Autodesk Fusion 360 part; units mm, degrees
(part 3 of 6)
sketch "Sketch1" plane through (0, 0, 0) normal (0, 1, 0) x (1, 0, 0)
  line L0 (-76.2, 57.15) -> (-76.2, -57.15) construction
  line L1 (76.2, -49.53) -> (76.2, 45.72) construction
  line L2 (-76.2, 57.15) -> (-38.1, 57.15) construction
  line L3 (-38.1, 57.15) -> (-38.1, 62.865) construction
  line L4 (-38.1, 62.865) -> (-19.05, 62.865) construction
  line L5 (-19.05, 62.865) -> (-19.05, 55.245) construction
  line L6 (-19.05, 55.245) -> (0, 55.245) construction
  line L7 (0, 55.245) -> (0, 45.72) construction
  line L8 (0, 45.72) -> (19.05, 45.72) construction
  line L9 (19.05, 45.72) -> (38.1, 45.72) construction
  line L10 (38.1, 45.72) -> (57.15, 45.72) construction
  line L11 (57.15, 45.72) -> (76.2, 45.72) construction
  line L12 (-57.15, 57.15) -> (-57.15, 38.1) construction
  line L13 (-57.15, 38.1) -> (-76.2, 38.1) construction
  line L14 (-38.1, 57.15) -> (-38.1, -38.1) construction
  line L15 (-38.1, -38.1) -> (-76.2, -38.1) construction
  line L16 (-57.15, 38.1) -> (-76.2, 57.15) construction
  line L17 (-76.2, 38.1) -> (-57.15, 57.15) construction
  line L18 (-19.05, 55.245) -> (-19.05, 43.815) construction
  line L19 (-19.05, 43.815) -> (-38.1, 43.815) construction
  line L20 (-38.1, 43.815) -> (-19.05, 62.865) construction
  line L21 (-19.05, 43.815) -> (-38.1, 62.865) construction
  line L22 (-19.05, 43.815) -> (-19.05, -32.385) construction
  line L23 (-19.05, -32.385) -> (-38.1, -32.385) construction
  line L24 (0, 45.72) -> (0, 36.195) construction
  line L25 (0, 36.195) -> (-19.05, 36.195) construction
  line L26 (0, 36.195) -> (-19.05, 55.245) construction
  line L27 (0, 55.245) -> (-19.05, 36.195) construction
  line L28 (0, 36.195) -> (0, -59.055) construction
  line L29 (0, -59.055) -> (-19.05, -59.055) construction
  line L30 (-19.05, -59.055) -> (-19.05, -32.385) construction
  line L31 (19.05, 45.72) -> (19.05, 26.67) construction
  line L32 (19.05, 26.67) -> (0, 26.67) construction
  line L33 (38.1, 45.72) -> (38.1, -68.58) construction
  line L34 (38.1, -68.58) -> (0, -68.58) construction
  line L35 (0, -68.58) -> (0, -59.055) construction
  line L36 (38.1, -68.58) -> (57.15, -68.58) construction
  line L37 (57.15, -68.58) -> (57.15, -49.53) construction
  line L38 (57.15, -49.53) -> (76.2, -49.53) construction
  line L39 (57.15, -49.53) -> (38.1, -49.53) construction
  line L40 (-76.2, -57.15) -> (-19.05, -57.15) construction
  line L41 (38.1, 45.72) -> (38.1, 26.67) construction
  line L42 (38.1, 26.67) -> (38.1, 7.62) construction
  line L43 (38.1, 7.62) -> (76.2, 7.62) construction
  line L44 (38.1, 26.67) -> (57.15, 26.67) construction
  line L45 (57.15, 26.67) -> (57.15, 45.72) construction
  line L46 (57.15, 26.67) -> (38.1, 45.72) construction
  line L47 (38.1, 26.67) -> (57.15, 45.72) construction
  line L48 (57.15, 7.62) -> (57.15, -30.48) construction
  line L49 (57.15, -30.48) -> (38.1, -30.48) construction
  line L50 (38.1, -11.43) -> (57.15, -11.43) construction
  line L51 (57.15, -30.48) -> (76.2, -30.48) construction
  line L52 (38.1, 7.62) -> (57.15, -11.43) construction
  line L53 (57.15, 7.62) -> (38.1, -11.43) construction
  line L54 (38.1, -49.53) -> (57.15, -68.58) construction
  line L55 (57.15, -49.53) -> (38.1, -68.58) construction
  line L56 (19.05, 45.72) -> (0, 26.67) construction
  line L57 (19.05, 26.67) -> (0, 45.72) construction
  line L58 (38.1, -30.48) -> (76.2, -49.53) construction
  line L59 (76.2, -30.48) -> (38.1, -49.53) construction
  line L60 (57.15, -30.48) -> (57.15, -49.53) construction
  line L61 (57.15, 7.62) -> (76.2, -30.48) construction
  line L62 (76.2, 7.62) -> (57.15, -30.48) construction
  line L63 (57.15, -11.43) -> (76.2, -11.43) construction
  line L64 (-19.05, -59.055) -> (-19.05, -59.16) construction
  line L65 (-19.05, -59.16) -> (-19.115, -59.16) construction
  line L66 (-19.115, -59.16) -> (-19.2509, -58.6529) construction
  line L67 (-19.2509, -58.6529) -> (-18.7438, -58.517) construction
  line L68 (-18.7438, -58.517) -> (-37.1447, -63.4475) construction
  line L69 (-37.1447, -63.4475) -> (-32.2142, -81.8484) construction
  line L70 (-32.2142, -81.8484) -> (-13.8133, -76.9179) construction
  line L71 (-13.8133, -76.9179) -> (-18.7438, -58.517) construction
  line L72 (-37.1447, -63.4475) -> (-73.9464, -73.3085) construction
  line L73 (-73.9464, -73.3085) -> (-64.0854, -110.1103) construction
  line L74 (-64.0854, -110.1103) -> (-8.8828, -95.3188) construction
  line L75 (-8.8828, -95.3188) -> (-13.8133, -76.9179) construction
  line L76 (-18.7438, -58.517) -> (-32.2142, -81.8484) construction
  line L77 (-37.1447, -63.4475) -> (-13.8133, -76.9179) construction
  line L78 (-20.5292, -61.6095) -> (-34.0522, -65.233)
  line L79 (-34.0522, -65.233) -> (-30.4287, -78.7559)
  line L80 (-30.4287, -78.7559) -> (-16.9057, -75.1325)
  line L81 (-16.9057, -75.1325) -> (-20.5292, -61.6095)
  line L82 (-20.5292, -61.6095) -> (-30.4287, -78.7559) construction
  line L83 (-34.0522, -65.233) -> (-16.9057, -75.1325) construction
  line L84 (-48.8296, -83.6864) -> (-35.3066, -80.063)
  line L85 (-35.3066, -80.063) -> (-38.9301, -66.54)
  line L86 (-38.9301, -66.54) -> (-52.4531, -70.1635)
  line L87 (-52.4531, -70.1635) -> (-48.8296, -83.6864)
  line L88 (-67.2305, -88.6169) -> (-53.7075, -84.9935)
  line L89 (-53.7075, -84.9935) -> (-57.331, -71.4705)
  line L90 (-57.331, -71.4705) -> (-70.8539, -75.094)
  line L91 (-70.8539, -75.094) -> (-67.2305, -88.6169)
  line L92 (-25.4982, -97.1568) -> (-11.9752, -93.5333)
  line L93 (-11.9752, -93.5333) -> (-15.5987, -80.0104)
  line L94 (-15.5987, -80.0104) -> (-29.1217, -83.6338)
  line L95 (-29.1217, -83.6338) -> (-25.4982, -97.1568)
  line L96 (-43.8991, -102.0873) -> (-30.3761, -98.4638)
  line L97 (-30.3761, -98.4638) -> (-33.9996, -84.9409)
  line L98 (-33.9996, -84.9409) -> (-47.5226, -88.5643)
  line L99 (-47.5226, -88.5643) -> (-43.8991, -102.0873)
  line L100 (-62.3, -107.0178) -> (-48.777, -103.3943)
  line L101 (-48.777, -103.3943) -> (-52.4005, -89.8714)
  line L102 (-52.4005, -89.8714) -> (-65.9234, -93.4948)
  line L103 (-65.9234, -93.4948) -> (-62.3, -107.0178)
  line L104 (-59.675, 54.625) -> (-73.675, 54.625)
  line L105 (-73.675, 54.625) -> (-73.675, 40.625)
  line L106 (-73.675, 40.625) -> (-59.675, 40.625)
  line L107 (-59.675, 40.625) -> (-59.675, 54.625)
  line L108 (-59.675, 54.625) -> (-73.675, 40.625) construction
  line L109 (-73.675, 54.625) -> (-59.675, 40.625) construction
  line L110 (-21.575, 60.34) -> (-35.575, 60.34)
  line L111 (-35.575, 60.34) -> (-35.575, 46.34)
  line L112 (-35.575, 46.34) -> (-21.575, 46.34)
  line L113 (-21.575, 46.34) -> (-21.575, 60.34)
  line L114 (-21.575, 60.34) -> (-35.575, 46.34) construction
  line L115 (-35.575, 60.34) -> (-21.575, 46.34) construction
  line L116 (-2.525, 52.72) -> (-16.525, 52.72)
  line L117 (-16.525, 52.72) -> (-16.525, 38.72)
  line L118 (-16.525, 38.72) -> (-2.525, 38.72)
  line L119 (-2.525, 38.72) -> (-2.525, 52.72)
  line L120 (-2.525, 52.72) -> (-16.525, 38.72) construction
  line L121 (-16.525, 52.72) -> (-2.525, 38.72) construction
  line L122 (16.525, 43.195) -> (2.525, 43.195)
  line L123 (2.525, 43.195) -> (2.525, 29.195)
  line L124 (2.525, 29.195) -> (16.525, 29.195)
  line L125 (16.525, 29.195) -> (16.525, 43.195)
  line L126 (16.525, 43.195) -> (2.525, 29.195) construction
  line L127 (2.525, 43.195) -> (16.525, 29.195) construction
  line L128 (54.625, 43.195) -> (40.625, 43.195)
  line L129 (40.625, 43.195) -> (40.625, 29.195)
  line L130 (40.625, 29.195) -> (54.625, 29.195)
  line L131 (54.625, 29.195) -> (54.625, 43.195)
  line L132 (54.625, 43.195) -> (40.625, 29.195) construction
  line L133 (40.625, 43.195) -> (54.625, 29.195) construction
  line L134 (73.675, -4.43) -> (59.675, -4.43)
  line L135 (59.675, -4.43) -> (59.675, -18.43)
  line L136 (59.675, -18.43) -> (73.675, -18.43)
  line L137 (73.675, -18.43) -> (73.675, -4.43)
  line L138 (73.675, -4.43) -> (59.675, -18.43) construction
  line L139 (59.675, -4.43) -> (73.675, -18.43) construction
  line L140 (54.625, 5.095) -> (40.625, 5.095)
  line L141 (40.625, 5.095) -> (40.625, -8.905)
  line L142 (40.625, -8.905) -> (54.625, -8.905)
  line L143 (54.625, -8.905) -> (54.625, 5.095)
  line L144 (54.625, 5.095) -> (40.625, -8.905) construction
  line L145 (40.625, 5.095) -> (54.625, -8.905) construction
  line L146 (64.15, -33.005) -> (50.15, -33.005)
  line L147 (50.15, -33.005) -> (50.15, -47.005)
  line L148 (50.15, -47.005) -> (64.15, -47.005)
  line L149 (64.15, -47.005) -> (64.15, -33.005)
  line L150 (64.15, -33.005) -> (50.15, -47.005) construction
  line L151 (50.15, -33.005) -> (64.15, -47.005) construction
  line L152 (54.625, -52.055) -> (40.625, -52.055)
  line L153 (40.625, -52.055) -> (40.625, -66.055)
  line L154 (40.625, -66.055) -> (54.625, -66.055)
  line L155 (54.625, -66.055) -> (54.625, -52.055)
  line L156 (54.625, -52.055) -> (40.625, -66.055) construction
  line L157 (40.625, -52.055) -> (54.625, -66.055) construction
  line L158 (-57.15, -38.1) -> (-57.15, -57.15) construction
  line L159 (-38.1, -38.1) -> (-38.1, -57.15) construction
  line L160 (-38.1, -38.1) -> (-19.05, -38.1) construction
  line L161 (-19.05, -38.1) -> (-38.1, -57.15) construction
  line L162 (-38.1, -57.15) -> (-57.15, -38.1) construction
  line L163 (-57.15, -38.1) -> (-76.2, -57.15) construction
  line L164 (-76.2, -38.1) -> (-57.15, -57.15) construction
  line L165 (-57.15, -57.15) -> (-38.1, -38.1) construction
  line L166 (-38.1, -38.1) -> (-19.05, -57.15) construction
  line L167 (-54.625, 54.625) -> (-54.625, 40.625)
  line L168 (-54.625, 40.625) -> (-40.625, 40.625)
  line L169 (-40.625, 40.625) -> (-40.625, 54.625)
  line L170 (-40.625, 54.625) -> (-54.625, 54.625)
  line L171 (-73.675, 35.575) -> (-73.675, 21.575)
  line L172 (-73.675, 21.575) -> (-59.675, 21.575)
  line L173 (-59.675, 21.575) -> (-59.675, 35.575)
  line L174 (-59.675, 35.575) -> (-73.675, 35.575)
  line L175 (-54.625, 35.575) -> (-54.625, 21.575)
  line L176 (-54.625, 21.575) -> (-40.625, 21.575)
  line L177 (-40.625, 21.575) -> (-40.625, 35.575)
  line L178 (-40.625, 35.575) -> (-54.625, 35.575)
  line L179 (-73.675, 16.525) -> (-73.675, 2.525)
  line L180 (-73.675, 2.525) -> (-59.675, 2.525)
  line L181 (-59.675, 2.525) -> (-59.675, 16.525)
  line L182 (-59.675, 16.525) -> (-73.675, 16.525)
  line L183 (-54.625, 16.525) -> (-54.625, 2.525)
  line L184 (-54.625, 2.525) -> (-40.625, 2.525)
  line L185 (-40.625, 2.525) -> (-40.625, 16.525)
  line L186 (-40.625, 16.525) -> (-54.625, 16.525)
  line L187 (-73.675, -2.525) -> (-73.675, -16.525)
  line L188 (-73.675, -16.525) -> (-59.675, -16.525)
  line L189 (-59.675, -16.525) -> (-59.675, -2.525)
  line L190 (-59.675, -2.525) -> (-73.675, -2.525)
  line L191 (-54.625, -2.525) -> (-54.625, -16.525)
  line L192 (-54.625, -16.525) -> (-40.625, -16.525)
  line L193 (-40.625, -16.525) -> (-40.625, -2.525)
  line L194 (-40.625, -2.525) -> (-54.625, -2.525)
  line L195 (-73.675, -21.575) -> (-73.675, -35.575)
  line L196 (-73.675, -35.575) -> (-59.675, -35.575)
  line L197 (-59.675, -35.575) -> (-59.675, -21.575)
  line L198 (-59.675, -21.575) -> (-73.675, -21.575)
  line L199 (-54.625, -21.575) -> (-54.625, -35.575)
  line L200 (-54.625, -35.575) -> (-40.625, -35.575)
  line L201 (-40.625, -35.575) -> (-40.625, -21.575)
  line L202 (-40.625, -21.575) -> (-54.625, -21.575)
  line L203 (-35.575, 41.29) -> (-35.575, 27.29)
  line L204 (-35.575, 27.29) -> (-21.575, 27.29)
  line L205 (-21.575, 27.29) -> (-21.575, 41.29)
  line L206 (-21.575, 41.29) -> (-35.575, 41.29)
  line L207 (-35.575, 22.24) -> (-35.575, 8.24)
  line L208 (-35.575, 8.24) -> (-21.575, 8.24)
  line L209 (-21.575, 8.24) -> (-21.575, 22.24)
  line L210 (-21.575, 22.24) -> (-35.575, 22.24)
  line L211 (-35.575, 3.19) -> (-35.575, -10.81)
  line L212 (-35.575, -10.81) -> (-21.575, -10.81)
  line L213 (-21.575, -10.81) -> (-21.575, 3.19)
  line L214 (-21.575, 3.19) -> (-35.575, 3.19)
  line L215 (-35.575, -15.86) -> (-35.575, -29.86)
  line L216 (-35.575, -29.86) -> (-21.575, -29.86)
  line L217 (-21.575, -29.86) -> (-21.575, -15.86)
  line L218 (-21.575, -15.86) -> (-35.575, -15.86)
  line L219 (-16.525, 33.67) -> (-16.525, 19.67)
  line L220 (-16.525, 19.67) -> (-2.525, 19.67)
  line L221 (-2.525, 19.67) -> (-2.525, 33.67)
  line L222 (-2.525, 33.67) -> (-16.525, 33.67)
  line L223 (-16.525, 14.62) -> (-16.525, 0.62)
  line L224 (-16.525, 0.62) -> (-2.525, 0.62)
  line L225 (-2.525, 0.62) -> (-2.525, 14.62)
  line L226 (-2.525, 14.62) -> (-16.525, 14.62)
  line L227 (-16.525, -4.43) -> (-16.525, -18.43)
  line L228 (-16.525, -18.43) -> (-2.525, -18.43)
  line L229 (-2.525, -18.43) -> (-2.525, -4.43)
  line L230 (-2.525, -4.43) -> (-16.525, -4.43)
  line L231 (-16.525, -23.48) -> (-16.525, -37.48)
  line L232 (-16.525, -37.48) -> (-2.525, -37.48)
  line L233 (-2.525, -37.48) -> (-2.525, -23.48)
  line L234 (-2.525, -23.48) -> (-16.525, -23.48)
  line L235 (-16.525, -42.53) -> (-16.525, -56.53)
  line L236 (-16.525, -56.53) -> (-2.525, -56.53)
  line L237 (-2.525, -56.53) -> (-2.525, -42.53)
  line L238 (-2.525, -42.53) -> (-16.525, -42.53)
  line L239 (21.575, 43.195) -> (21.575, 29.195)
  line L240 (21.575, 29.195) -> (35.575, 29.195)
  line L241 (35.575, 29.195) -> (35.575, 43.195)
  line L242 (35.575, 43.195) -> (21.575, 43.195)
  line L243 (2.525, 24.145) -> (2.525, 10.145)
  line L244 (2.525, 10.145) -> (16.525, 10.145)
  line L245 (16.525, 10.145) -> (16.525, 24.145)
  line L246 (16.525, 24.145) -> (2.525, 24.145)
  line L247 (21.575, 24.145) -> (21.575, 10.145)
  line L248 (21.575, 10.145) -> (35.575, 10.145)
  line L249 (35.575, 10.145) -> (35.575, 24.145)
  line L250 (35.575, 24.145) -> (21.575, 24.145)
  line L251 (2.525, 5.095) -> (2.525, -8.905)
  line L252 (2.525, -8.905) -> (16.525, -8.905)
  line L253 (16.525, -8.905) -> (16.525, 5.095)
  line L254 (16.525, 5.095) -> (2.525, 5.095)
  line L255 (21.575, 5.095) -> (21.575, -8.905)
  line L256 (21.575, -8.905) -> (35.575, -8.905)
  line L257 (35.575, -8.905) -> (35.575, 5.095)
  line L258 (35.575, 5.095) -> (21.575, 5.095)
  line L259 (2.525, -13.955) -> (2.525, -27.955)
  line L260 (2.525, -27.955) -> (16.525, -27.955)
  line L261 (16.525, -27.955) -> (16.525, -13.955)
  line L262 (16.525, -13.955) -> (2.525, -13.955)
  line L263 (21.575, -13.955) -> (21.575, -27.955)
  line L264 (21.575, -27.955) -> (35.575, -27.955)
  line L265 (35.575, -27.955) -> (35.575, -13.955)
  line L266 (35.575, -13.955) -> (21.575, -13.955)
  line L267 (2.525, -33.005) -> (2.525, -47.005)
  line L268 (2.525, -47.005) -> (16.525, -47.005)
  line L269 (16.525, -47.005) -> (16.525, -33.005)
  line L270 (16.525, -33.005) -> (2.525, -33.005)
  line L271 (21.575, -33.005) -> (21.575, -47.005)
  line L272 (21.575, -47.005) -> (35.575, -47.005)
  line L273 (35.575, -47.005) -> (35.575, -33.005)
  line L274 (35.575, -33.005) -> (21.575, -33.005)
  line L275 (2.525, -52.055) -> (2.525, -66.055)
  line L276 (2.525, -66.055) -> (16.525, -66.055)
  line L277 (16.525, -66.055) -> (16.525, -52.055)
  line L278 (16.525, -52.055) -> (2.525, -52.055)
  line L279 (21.575, -52.055) -> (21.575, -66.055)
  line L280 (21.575, -66.055) -> (35.575, -66.055)
  line L281 (35.575, -66.055) -> (35.575, -52.055)
  line L282 (35.575, -52.055) -> (21.575, -52.055)
  line L283 (59.675, 43.195) -> (59.675, 29.195)
  line L284 (59.675, 29.195) -> (73.675, 29.195)
  line L285 (73.675, 29.195) -> (73.675, 43.195)
  line L286 (73.675, 43.195) -> (59.675, 43.195)
  line L287 (40.625, 24.145) -> (40.625, 10.145)
  line L288 (40.625, 10.145) -> (54.625, 10.145)
  line L289 (54.625, 10.145) -> (54.625, 24.145)
  line L290 (54.625, 24.145) -> (40.625, 24.145)
  line L291 (59.675, 24.145) -> (59.675, 10.145)
  line L292 (59.675, 10.145) -> (73.675, 10.145)
  line L293 (73.675, 10.145) -> (73.675, 24.145)
  line L294 (73.675, 24.145) -> (59.675, 24.145)
  line L295 (40.625, -13.955) -> (40.625, -27.955)
  line L296 (40.625, -27.955) -> (54.625, -27.955)
  line L297 (54.625, -27.955) -> (54.625, -13.955)
  line L298 (54.625, -13.955) -> (40.625, -13.955)
  line L299 (-40.625, -40.625) -> (-54.625, -40.625)
  line L300 (-54.625, -40.625) -> (-54.625, -54.625)
  line L301 (-54.625, -54.625) -> (-40.625, -54.625)
  line L302 (-40.625, -54.625) -> (-40.625, -40.625)
  line L303 (-40.625, -40.625) -> (-54.625, -54.625) construction
  line L304 (-54.625, -40.625) -> (-40.625, -54.625) construction
  line L305 (-47.625, -47.625) -> (-47.625, -48.225) construction
  line L306 (-47.625, -48.225) -> (-65.625, -48.225) construction
  line L307 (-62.625, -41.975) -> (-68.625, -41.975)
  line L308 (-68.625, -41.975) -> (-68.625, -54.475)
  line L309 (-68.625, -54.475) -> (-62.625, -54.475)
  line L310 (-62.625, -54.475) -> (-62.625, -41.975)
  line L311 (-62.625, -41.975) -> (-68.625, -54.475) construction
  line L312 (-68.625, -41.975) -> (-62.625, -54.475) construction
  line L313 (-62.625, -48.225) -> (-62.625, -49.06) construction
  line L314 (-62.625, -49.06) -> (-54.625, -49.06) construction
  line L315 (-62.625, -47.81) -> (-54.625, -47.81)
  line L316 (-62.625, -50.31) -> (-54.625, -50.31)
  line L317 (-65.625, -54.475) -> (-66.475, -54.475) construction
  line L318 (-66.475, -54.475) -> (-64.775, -54.475)
  line L319 (-64.775, -54.475) -> (-64.775, -55.475)
  line L320 (-64.775, -55.475) -> (-66.475, -55.475)
  line L321 (-66.475, -55.475) -> (-66.475, -54.475)
  line L322 (-32.625, -50.31) -> (-40.625, -50.31)
  line L323 (-32.625, -47.81) -> (-40.625, -47.81)
  line L324 (-26.625, -41.975) -> (-26.625, -54.475)
  line L325 (-26.625, -54.475) -> (-32.625, -54.475)
  line L326 (-32.625, -41.975) -> (-26.625, -41.975)
  line L327 (-32.625, -54.475) -> (-32.625, -41.975)
  line L328 (-28.775, -55.475) -> (-28.775, -54.475)
  line L329 (-28.775, -54.475) -> (-30.475, -54.475)
  line L330 (-30.475, -55.475) -> (-28.775, -55.475)
  line L331 (-30.475, -54.475) -> (-30.475, -55.475)
  line L332 (57.15, -40.005) -> (57.15, -40.605) construction
  line L333 (57.15, -40.605) -> (45.15, -40.605) construction
  line L334 (48.15, -34.355) -> (42.15, -34.355)
  line L335 (42.15, -34.355) -> (42.15, -46.855)
  line L336 (42.15, -46.855) -> (48.15, -46.855)
  line L337 (48.15, -46.855) -> (48.15, -34.355)
  line L338 (48.15, -34.355) -> (42.15, -46.855) construction
  line L339 (42.15, -34.355) -> (48.15, -46.855) construction
  line L340 (48.15, -40.605) -> (48.15, -41.44) construction
  line L341 (48.15, -41.44) -> (50.15, -41.44) construction
  line L342 (48.15, -40.19) -> (50.15, -40.19)
  line L343 (48.15, -42.69) -> (50.15, -42.69)
  line L344 (45.15, -46.855) -> (44.3, -46.855) construction
  line L345 (44.3, -46.855) -> (46, -46.855)
  line L346 (46, -46.855) -> (46, -47.855)
  line L347 (46, -47.855) -> (44.3, -47.855)
  line L348 (44.3, -47.855) -> (44.3, -46.855)
  line L349 (72.15, -34.355) -> (72.15, -46.855)
  line L350 (72.15, -46.855) -> (66.15, -46.855)
  line L351 (66.15, -46.855) -> (66.15, -34.355)
  line L352 (66.15, -34.355) -> (72.15, -34.355)
  line L353 (70, -47.855) -> (70, -46.855)
  line L354 (70, -46.855) -> (68.3, -46.855)
  line L355 (68.3, -47.855) -> (70, -47.855)
  line L356 (68.3, -46.855) -> (68.3, -47.855)
  line L357 (66.15, -42.69) -> (64.15, -42.69)
  line L358 (66.15, -40.19) -> (64.15, -40.19)
  line L359 (66.675, -11.43) -> (67.275, -11.43) construction
  line L360 (67.275, -11.43) -> (67.275, -23.43) construction
  line L361 (73.525, -20.43) -> (61.025, -20.43)
  line L362 (61.025, -20.43) -> (61.025, -26.43)
  line L363 (61.025, -26.43) -> (73.525, -26.43)
  line L364 (73.525, -26.43) -> (73.525, -20.43)
  line L365 (73.525, -20.43) -> (61.025, -26.43) construction
  line L366 (61.025, -20.43) -> (73.525, -26.43) construction
  line L367 (67.275, -20.43) -> (68.11, -20.43) construction
  line L368 (68.11, -20.43) -> (68.11, -18.43) construction
  line L369 (66.86, -18.43) -> (66.86, -20.43)
  line L370 (69.36, -18.43) -> (69.36, -20.43)
  line L371 (73.525, -23.43) -> (73.525, -24.28) construction
  line L372 (73.525, -24.28) -> (74.525, -24.28)
  line L373 (74.525, -24.28) -> (74.525, -22.58)
  line L374 (74.525, -22.58) -> (73.525, -22.58)
  line L375 (73.525, -22.58) -> (73.525, -24.28)
  line L376 (61.025, 3.57) -> (73.525, 3.57)
  line L377 (73.525, 3.57) -> (73.525, -2.43)
  line L378 (73.525, -2.43) -> (61.025, -2.43)
  line L379 (61.025, -2.43) -> (61.025, 3.57)
  line L380 (66.86, -4.43) -> (66.86, -2.43)
  line L381 (69.36, -4.43) -> (69.36, -2.43)
  line L382 (73.525, 1.42) -> (74.525, 1.42)
  line L383 (74.525, 1.42) -> (74.525, -0.28)
  line L384 (73.525, -0.28) -> (73.525, 1.42)
  line L385 (74.525, -0.28) -> (73.525, -0.28)
  line L386 (-76.2, 57.15) -> (-86.56, 57.15) construction
  line L387 (-86.56, 57.15) -> (-86.56, 59.625) construction
  line L388 (-38.1, 57.15) -> (-40.575, 57.15) construction
  line L389 (-40.575, 57.15) -> (-40.575, 59.625) construction
  line L390 (-38.1, 62.865) -> (-38.1, 65.34) construction
  line L391 (-38.1, 65.34) -> (-40.575, 65.34) construction
  line L392 (-19.05, 62.865) -> (-19.05, 65.34) construction
  line L393 (-19.05, 65.34) -> (-16.575, 65.34) construction
  line L394 (-19.05, 55.245) -> (-16.575, 55.245) construction
  line L395 (-16.575, 55.245) -> (-16.575, 57.72) construction
  line L396 (0, 55.245) -> (2.475, 55.245) construction
  line L397 (2.475, 55.245) -> (2.475, 57.72) construction
  line L398 (0, 45.72) -> (2.475, 45.72) construction
  line L399 (2.475, 45.72) -> (2.475, 48.195) construction
  line L400 (76.2, 45.72) -> (76.2, 48.195) construction
  line L401 (76.2, 48.195) -> (78.675, 48.195) construction
  line L402 (76.2, -49.53) -> (76.2, -52.005) construction
  line L403 (76.2, -52.005) -> (78.675, -52.005) construction
  line L404 (57.15, -49.53) -> (59.625, -49.53) construction
  line L405 (59.625, -49.53) -> (59.625, -52.005) construction
  line L406 (57.15, -68.58) -> (57.15, -71.055) construction
  line L407 (57.15, -71.055) -> (59.625, -71.055) construction
  line L408 (0, -68.58) -> (-2.475, -68.58) construction
  line L409 (-2.475, -68.58) -> (-2.475, -71.055) construction
  line L410 (-8.8828, -95.3188) -> (-6.4921, -94.6782) construction
  line L411 (-6.4921, -94.6782) -> (-5.8515, -97.0689) construction
  line L412 (-64.0854, -110.1103) -> (-74.0924, -112.7917) construction
  line L413 (-74.0924, -112.7917) -> (-73.4518, -115.1823) construction
  line L414 (-73.9464, -73.3085) -> (-83.9534, -75.9899) construction
  line L415 (-83.9534, -75.9899) -> (-84.594, -73.5992) construction
  line L416 (-76.2, -57.15) -> (-76.2, -59.625) construction
  line L417 (-76.2, -59.625) -> (-86.56, -59.625) construction
  line L418 (-86.56, 59.625) -> (-40.575, 59.625)
  line L419 (-40.575, 59.625) -> (-40.575, 65.34)
  line L420 (-40.575, 65.34) -> (-16.575, 65.34)
  line L421 (-16.575, 65.34) -> (-16.575, 57.72)
  line L422 (-16.575, 57.72) -> (2.475, 57.72)
  line L423 (2.475, 57.72) -> (2.475, 48.195)
  line L424 (2.475, 48.195) -> (78.675, 48.195)
  line L425 (78.675, 48.195) -> (78.675, -52.005)
  line L426 (78.675, -52.005) -> (59.625, -52.005)
  line L427 (59.625, -52.005) -> (59.625, -71.055)
  line L428 (59.625, -71.055) -> (-2.475, -71.055)
  line L429 (-2.475, -71.055) -> (-5.8515, -97.0689)
  line L430 (-5.8515, -97.0689) -> (-73.4518, -115.1823)
  line L431 (-73.4518, -115.1823) -> (-84.594, -73.5992)
  line L432 (-86.56, -59.625) -> (-84.594, -73.5992)
  line L433 (-86.56, -59.625) -> (-86.56, 59.625)
  point P0 (-25.479, -70.1827)
  point P1 (-66.675, 47.625)
  point P2 (-28.575, 53.34)
  point P3 (-9.525, 45.72)
  point P4 (9.525, 36.195)
  point P5 (47.625, 36.195)
  point P6 (66.675, -11.43)
  point P7 (47.625, -1.905)
  point P8 (57.15, -40.005)
  point P9 (47.625, -59.055)
  point P10 (-47.625, -47.625)
  point P11 (-65.625, -48.225)
  point P12 (45.15, -40.605)
  point P13 (67.275, -23.43)
  dimension "d67" = 114.3
  dimension "d68" = 38.1
  dimension "d69" = 5.715
  dimension "d70" = 19.05
  dimension "d71" = 7.62
  dimension "d72" = 19.05
  dimension "d73" = 9.525
  dimension "d74" = 19.05
  dimension "d75" = 19.05
  dimension "d76" = 19.05
  dimension "d77" = 19.05
  dimension "d78" = 95.25
  dimension "d79" = 11.43
  dimension "d80" = 76.2
  dimension "d81" = 9.525
  dimension "d82" = 95.25
  dimension "d83" = 19.05
  dimension "d84" = 19.05
  dimension "d85" = 114.3
  dimension "d86" = 38.1
  dimension "d87" = 19.05
  dimension "d88" = 19.05
  dimension "d89" = 19.05
  dimension "d90" = 19.05
  dimension "d91" = 19.05
  dimension "d92" = 38.1
  dimension "d93" = 0.105
  dimension "d94" = 0.065
  dimension "d95" = 0.525
  dimension "d96" = 0.525
  dimension "d97" = 19.05
  dimension "d98" = 19.05
  dimension "d99" = 38.1
  dimension "d100" = 38.1
  dimension "d101" = 57.15
  dimension "d102" = 14
  dimension "d103" = 14
  dimension "d107" = 19.05
  dimension "d108" = 14
  dimension "d109" = 14
  dimension "d110" = 14
  dimension "d111" = 14
  dimension "d112" = 14
  dimension "d113" = 14
  dimension "d114" = 14
  dimension "d115" = 14
  dimension "d116" = 14
  dimension "d117" = 14
  dimension "d118" = 14
  dimension "d119" = 14
  dimension "d120" = 14
  dimension "d121" = 14
  dimension "d122" = 14
  dimension "d123" = 14
  dimension "d124" = 14
  dimension "d125" = 14
  dimension "d128" = 19.05
  dimension "d132" = 0
  dimension "d136" = 0
  dimension "d140" = 19.05
  dimension "d144" = 19.05
  dimension "d148" = 0
  dimension "d150" = 14
  dimension "d151" = 14
  dimension "d152" = 0.6
  dimension "d153" = 18
  dimension "d154" = 6
  dimension "d155" = 12.5
  dimension "d156" = 0.835
  dimension "d157" = 1.25
  dimension "d158" = 0.85
  dimension "d159" = 1.7
  dimension "d160" = 1
  dimension "d161" = 0.6
  dimension "d162" = 12
  dimension "d163" = 6
  dimension "d164" = 12.5
  dimension "d165" = 0.835
  dimension "d166" = 1.25
  dimension "d167" = 0.85
  dimension "d168" = 1.7
  dimension "d169" = 1
  dimension "d170" = 0.6
  dimension "d171" = 12
  dimension "d172" = 12.5
  dimension "d173" = 6
  dimension "d174" = 0.835
  dimension "d175" = 1.25
  dimension "d176" = 0.85
  dimension "d177" = 1
  dimension "d178" = 1.7
  dimension "d179" = 10.36
  dimension "d180" = 2.475
  dimension "d181" = 2.475
  dimension "d182" = 2.475
  dimension "d183" = 2.475
  dimension "d184" = 2.475
  dimension "d185" = 2.475
  dimension "d186" = 2.475
  dimension "d187" = 2.475
  dimension "d188" = 2.475
  dimension "d189" = 2.475
  dimension "d190" = 2.475
  dimension "d191" = 2.475
  dimension "d192" = 2.475
  dimension "d193" = 2.475
  dimension "d194" = 2.475
  dimension "d195" = 2.475
  dimension "d196" = 2.475
  dimension "d197" = 2.475
  dimension "d198" = 2.475
  dimension "d199" = 2.475
  dimension "d200" = 2.475
  dimension "d201" = 2.475
  dimension "d202" = 2.475
  dimension "d203" = 2.475
  dimension "d204" = 2.475
  dimension "d205" = 10.36
  dimension "d206" = 2.475
  dimension "d207" = 10.36
  dimension "d208" = 2.475
  dimension "d209" = 2.475
  dimension "d210" = 10.36
  constraint parallel L0 L1
  constraint perpendicular L0 L2
  constraint perpendicular L3 L4
  constraint perpendicular L4 L5
  constraint perpendicular L3 L6
  constraint perpendicular L6 L7
  constraint perpendicular L3 L8
  constraint perpendicular L1 L9
  constraint perpendicular L1 L10
  constraint perpendicular L1 L11
  constraint midpoint L2 L12.start
  constraint perpendicular L2 L12
  constraint coincident L0 L13.end
  constraint perpendicular L0 L13
  constraint perpendicular L2 L14
  constraint coincident L0 L15.end
  constraint perpendicular L0 L15
  constraint perpendicular L6 L18
  constraint coincident L14 L19.end
  constraint perpendicular L14 L19
  constraint perpendicular L20 L21
  constraint perpendicular L19 L22
  constraint coincident L14 L23.end
  constraint perpendicular L14 L23
  constraint perpendicular L8 L24
  constraint coincident L22 L25.end
  constraint perpendicular L22 L25
  constraint perpendicular L25 L28
  constraint perpendicular L28 L29
  constraint perpendicular L9 L31
  constraint coincident L28 L32.end
  constraint perpendicular L28 L32
  constraint perpendicular L33 L34
  constraint perpendicular L29 L35
  constraint perpendicular L33 L36
  constraint perpendicular L1 L38
  constraint coincident L33 L39.end
  constraint perpendicular L33 L39
  constraint coincident L30 L40.end
  constraint perpendicular L10 L41
  constraint perpendicular L10 L42
  constraint coincident L1 L43.end
  constraint perpendicular L1 L43
  constraint perpendicular L42 L44
  constraint midpoint L43 L48.start
  constraint perpendicular L43 L48
  constraint coincident L33 L49.end
  constraint perpendicular L33 L49
  constraint midpoint L33 L50.start
  constraint midpoint L48 L50.end
  constraint coincident L1 L51.end
  constraint perpendicular L1 L51
  constraint perpendicular L52 L53
  constraint perpendicular L53 L54
  constraint perpendicular L54 L55
  constraint coincident L1 L63.end
  constraint perpendicular L1 L63
  constraint perpendicular L29 L64
  constraint perpendicular L66 L67
  constraint perpendicular L64 L65
  constraint collinear L67 L68
  constraint perpendicular L69 L72
  constraint perpendicular L72 L73
  constraint perpendicular L73 L74
  constraint perpendicular L70 L75
  constraint perpendicular L76 L77
  constraint perpendicular L78 L79
  constraint parallel L78 L80
  constraint parallel L79 L81
  constraint coincident L82 P0
  constraint coincident L83 P0
  constraint midpoint L77 P0
  constraint horizontal L104
  constraint perpendicular L104 L105
  constraint parallel L104 L106
  constraint parallel L105 L107
  constraint coincident L108 P1
  constraint coincident L109 P1
  constraint midpoint L16 P1
  constraint horizontal L110
  constraint perpendicular L110 L111
  constraint parallel L110 L112
  constraint parallel L111 L113
  constraint coincident L114 P2
  constraint coincident L115 P2
  constraint midpoint L20 P2
  constraint horizontal L116
  constraint perpendicular L116 L117
  constraint parallel L116 L118
  constraint parallel L117 L119
  constraint coincident L120 P3
  constraint coincident L121 P3
  constraint midpoint L26 P3
  constraint horizontal L122
  constraint perpendicular L122 L123
  constraint parallel L122 L124
  constraint parallel L123 L125
  constraint coincident L126 P4
  constraint coincident L127 P4
  constraint midpoint L56 P4
  constraint horizontal L128
  constraint perpendicular L128 L129
  constraint parallel L128 L130
  constraint parallel L129 L131
  constraint coincident L132 P5
  constraint coincident L133 P5
  constraint midpoint L47 P5
  constraint horizontal L134
  constraint perpendicular L134 L135
  constraint parallel L134 L136
  constraint parallel L135 L137
  constraint coincident L138 P6
  constraint coincident L139 P6
  constraint midpoint L63 P6
  constraint horizontal L140
  constraint perpendicular L140 L141
  constraint parallel L140 L142
  constraint parallel L141 L143
  constraint coincident L144 P7
  constraint coincident L145 P7
  constraint midpoint L53 P7
  constraint horizontal L146
  constraint perpendicular L146 L147
  constraint parallel L146 L148
  constraint parallel L147 L149
  constraint coincident L150 P8
  constraint coincident L151 P8
  constraint midpoint L59 P8
  constraint horizontal L152
  constraint perpendicular L152 L153
  constraint parallel L152 L154
  constraint parallel L153 L155
  constraint coincident L156 P9
  constraint coincident L157 P9
  constraint midpoint L54 P9
  constraint midpoint L15 L158.start
  constraint coincident L40 L158.end
  constraint perpendicular L40 L158
  constraint coincident L40 L159.end
  constraint perpendicular L40 L159
  constraint coincident L30 L160.end
  constraint perpendicular L30 L160
  constraint perpendicular L161 L162
  constraint horizontal L299
  constraint perpendicular L299 L300
  constraint parallel L299 L301
  constraint parallel L300 L302
  constraint coincident L303 P10
  constraint coincident L304 P10
  constraint midpoint L162 P10
  constraint coincident P10 L305.start
  constraint vertical L305
  constraint perpendicular L158 L306
  constraint horizontal L307
  constraint perpendicular L307 L308
  constraint parallel L307 L309
  constraint parallel L308 L310
  constraint coincident L311 P11
  constraint coincident L312 P11
  constraint coincident P11 L306.end
  constraint midpoint L310 L313.start
  constraint coincident L310 L313.end
  constraint perpendicular L306 L313
  constraint coincident L300 L314.end
  constraint perpendicular L300 L314
  constraint coincident L310 L315.start
  constraint coincident L300 L315.end
  constraint perpendicular L300 L315
  constraint symmetric L314 L315.start L316.start
  constraint symmetric L314 L315.end L316.end
  constraint midpoint L309 L317.start
  constraint coincident L309 L317.end
  constraint horizontal L318
  constraint vertical L319
  constraint horizontal L320
  constraint vertical L321
  constraint symmetric L305 L307.start L326.start
  constraint symmetric L305 L307.end L324.start
  constraint symmetric L305 L308.end L324.end
  constraint symmetric L305 L309.end L325.end
  constraint symmetric L305 L315.start L323.start
  constraint symmetric L305 L315.end L323.end
  constraint symmetric L305 L316.start L322.start
  constraint symmetric L305 L316.end L322.end
  constraint symmetric L305 L317.end L328.end
  constraint symmetric L305 L318.end L329.end
  constraint symmetric L305 L319.end L330.start
  constraint symmetric L305 L320.end L328.start
  constraint coincident P8 L332.start
  constraint coincident L60 L332.end
  constraint perpendicular L332 L333
  constraint horizontal L334
  constraint perpendicular L334 L335
  constraint parallel L334 L336
  constraint parallel L335 L337
  constraint coincident L338 P12
  constraint coincident L339 P12
  constraint coincident P12 L333.end
  constraint midpoint L337 L340.start
  constraint coincident L337 L340.end
  constraint coincident L147 L341.end
  constraint perpendicular L147 L341
  constraint coincident L337 L342.start
  constraint coincident L147 L342.end
  constraint perpendicular L147 L342
  constraint symmetric L341 L342.start L343.start
  constraint symmetric L341 L342.end L343.end
  constraint midpoint L336 L344.start
  constraint coincident L336 L344.end
  constraint horizontal L345
  constraint vertical L346
  constraint horizontal L347
  constraint vertical L348
  constraint symmetric L60 L334.start L351.end
  constraint symmetric L60 L334.end L349.start
  constraint symmetric L60 L335.end L349.end
  constraint symmetric L60 L336.end L350.end
  constraint symmetric L60 L342.start L358.start
  constraint symmetric L60 L342.end L358.end
  constraint symmetric L60 L343.start L357.start
  constraint symmetric L60 L343.end L357.end
  constraint symmetric L60 L344.end L353.end
  constraint symmetric L60 L345.end L354.end
  constraint symmetric L60 L346.end L355.start
  constraint symmetric L60 L347.end L353.start
  constraint coincident P6 L359.start
  constraint coincident L63 L359.end
  constraint perpendicular L136 L360
  constraint horizontal L361
  constraint perpendicular L361 L362
  constraint parallel L361 L363
  constraint parallel L362 L364
  constraint coincident L365 P13
  constraint coincident L366 P13
  constraint coincident P13 L360.end
  constraint midpoint L361 L367.start
  constraint coincident L361 L367.end
  constraint coincident L136 L368.end
  constraint perpendicular L136 L368
  constraint coincident L136 L369.start
  constraint coincident L361 L369.end
  constraint perpendicular L361 L369
  constraint symmetric L368 L369.start L370.start
  constraint symmetric L368 L369.end L370.end
  constraint midpoint L364 L371.start
  constraint parallel L364 L371
  constraint horizontal L372
  constraint vertical L373
  constraint horizontal L374
  constraint vertical L375
  constraint symmetric L63 L361.start L377.end
  constraint symmetric L63 L361.end L378.end
  constraint symmetric L63 L362.end L376.start
  constraint symmetric L63 L363.end L376.end
  constraint symmetric L63 L369.start L380.start
  constraint symmetric L63 L369.end L380.end
  constraint symmetric L63 L370.start L381.start
  constraint symmetric L63 L370.end L381.end
  constraint symmetric L63 L371.end L382.start
  constraint symmetric L63 L372.end L382.end
  constraint symmetric L63 L373.end L383.end
  constraint symmetric L63 L374.end L384.start
  constraint perpendicular L0 L386
  constraint perpendicular L2 L387
  constraint perpendicular L3 L388
  constraint perpendicular L388 L389
  constraint perpendicular L4 L390
  constraint perpendicular L3 L391
  constraint perpendicular L4 L392
  constraint perpendicular L5 L393
  constraint coincident L6 L394.end
  constraint perpendicular L394 L395
  constraint perpendicular L7 L396
  constraint perpendicular L6 L397
  constraint coincident L8 L398.end
  constraint perpendicular L398 L399
  constraint perpendicular L11 L400
  constraint perpendicular L1 L401
  constraint perpendicular L38 L402
  constraint perpendicular L402 L403
  constraint coincident L38 L404.end
  constraint perpendicular L404 L405
  constraint perpendicular L36 L406
  constraint perpendicular L37 L407
  constraint perpendicular L35 L408
  constraint perpendicular L34 L409
  constraint perpendicular L75 L410
  constraint perpendicular L74 L411
  constraint perpendicular L73 L412
  constraint perpendicular L74 L413
  constraint perpendicular L73 L414
  constraint perpendicular L72 L415
  constraint perpendicular L40 L416
  constraint perpendicular L0 L417
  measures "d67" distance of L0.start L0.end
  measures "d68" distance of L0.start L2.end
  measures "d69" distance of L2.end L3.end
  measures "d70" distance of L3.end L4.end
  measures "d71" distance of L4.end L5.end
  measures "d72" distance of L5.end L6.end
  measures "d73" distance of L6.end L7.end
  measures "d74" distance of L7.end L8.end
  measures "d75" distance of L8.end L9.end
  measures "d76" distance of L9.end L10.end
  measures "d77" distance of L12.start L12.end
  measures "d78" distance of L2.end L14.end
  measures "d79" distance of L5.end L18.end
  measures "d80" distance of L18.end L22.end
  measures "d81" distance of L7.end L24.end
  measures "d82" distance of L24.end L28.end
  measures "d83" distance of L28.end L29.end
  measures "d84" distance of L8.end L31.end
  measures "d85" distance of L9.end L33.end
  measures "d86" distance of L33.end L34.end
  measures "d87" distance of L33.end L36.end
  measures "d88" distance of L36.end L37.end
  measures "d89" distance of L9.end L41.end
  measures "d90" distance of L41.end L42.end
  measures "d91" distance of L41.end L44.end
  measures "d92" distance of L48.start L48.end
  measures "d93" distance of L29.end L64.end
  measures "d94" distance of L64.end L65.end
  measures "d95" distance of L65.end L66.end
  measures "d96" distance of L66.end L67.end
  measures "d97" distance of L67.end L68.end
  measures "d98" distance of L67.end L70.end
  measures "d99" distance of L68.end L72.end
  measures "d100" distance of L72.end L73.end
  measures "d101" distance of L73.end L74.end
  measures "d102" distance of L79.end L80.end
  measures "d103" distance of L78.end L79.end
  measures "d108" distance of L105.end L106.end
  measures "d109" distance of L104.end L105.end
  measures "d110" distance of L111.end L112.end
  measures "d111" distance of L110.end L111.end
  measures "d112" distance of L117.end L118.end
  measures "d113" distance of L116.end L117.end
  measures "d114" distance of L123.end L124.end
  measures "d115" distance of L122.end L123.end
  measures "d116" distance of L129.end L130.end
  measures "d117" distance of L128.end L129.end
  measures "d118" distance of L135.end L136.end
  measures "d119" distance of L134.end L135.end
  measures "d120" distance of L141.end L142.end
  measures "d121" distance of L140.end L141.end
  measures "d122" distance of L147.end L148.end
  measures "d123" distance of L146.end L147.end
  measures "d124" distance of L153.end L154.end
  measures "d125" distance of L152.end L153.end
  measures "d150" distance of L300.end L301.end
  measures "d151" distance of L299.end L300.end
  measures "d152" distance of P10 L305.end
  measures "d153" distance of L305.end P11
  measures "d154" distance of L308.end L309.end
  measures "d155" distance of L307.end L308.end
  measures "d156" distance of L313.start L313.end
  measures "d157" distance of L314 L315
  measures "d158" distance of L317.start L317.end
  measures "d159" distance of L317.end L318.end
  measures "d160" distance of L317.end L320.end
  measures "d161" distance of P8 L332.end
  measures "d162" distance of L332.end P12
  measures "d163" distance of L335.end L336.end
  measures "d164" distance of L334.end L335.end
  measures "d165" distance of L340.start L340.end
  measures "d166" distance of L341 L342
  measures "d167" distance of L344.start L344.end
  measures "d168" distance of L344.end L345.end
  measures "d169" distance of L344.end L347.end
  measures "d170" distance of P6 L359.end
  measures "d171" distance of L359.end P13
  measures "d172" distance of L362.end L363.end
  measures "d173" distance of L361.end L362.end
  measures "d174" distance of L367.start L367.end
  measures "d175" distance of L368 L369
  measures "d176" distance of L371.start L371.end
  measures "d177" distance of L371.end L372.end
  measures "d178" distance of L371.end L374.end
  measures "d179" distance of L0.start L386.end
  measures "d180" distance of L386.end L387.end
  measures "d181" distance of L2.end L388.end
  measures "d182" distance of L388.end L389.end
  measures "d183" distance of L3.end L390.end
  measures "d184" distance of L390.end L391.end
  measures "d185" distance of L4.end L392.end
  measures "d186" distance of L392.end L393.end
  measures "d187" distance of L5.end L394.end
  measures "d188" distance of L394.end L395.end
  measures "d189" distance of L6.end L396.end
  measures "d190" distance of L396.end L397.end
  measures "d191" distance of L7.end L398.end
  measures "d192" distance of L398.end L399.end
  measures "d193" distance of L1.end L400.end
  measures "d194" distance of L400.end L401.end
  measures "d195" distance of L1.start L402.end
  measures "d196" distance of L402.end L403.end
  measures "d197" distance of L37.end L404.end
  measures "d198" distance of L404.end L405.end
  measures "d199" distance of L36.end L406.end
  measures "d200" distance of L406.end L407.end
  measures "d201" distance of L34.end L408.end
  measures "d202" distance of L408.end L409.end
  measures "d203" distance of L74.end L410.end
  measures "d204" distance of L410.end L411.end
  measures "d205" distance of L73.end L412.end
  measures "d206" distance of L412.end L413.end
  measures "d207" distance of L72.end L414.end
  measures "d208" distance of L414.end L415.end
  measures "d209" distance of L0.end L416.end
  measures "d210" distance of L416.end L417.end
extrude "Extrude1" add sketch "Sketch1" along normal blind 1.5
fillet "Fillet1" radius 0.25 243 edges at (-70.8539, 0.75, 75.094) (-65.9234, 0.75, 93.4948) (-47.5226, 0.75, 88.5643) (-52.4531, 0.75, 70.1635) (-29.1217, 0.75, 83.6338) (-34.0522, 0.75, 65.233) (-57.331, 0.75, 71.4705) (-52.4005, 0.75, 89.8714) (-33.9996, 0.75, 84.9409) (-15.5987, 0.75, 80.0104) (-20.5292, 0.75, 61.6095) (-38.9301, 0.75, 66.54) (-16.9057, 0.75, 75.1325) (-11.9752, 0.75, 93.5333) (-30.3761, 0.75, 98.4638) (-35.3066, 0.75, 80.063) (-53.7075, 0.75, 84.9935) (-48.777, 0.75, 103.3943) (-30.4287, 0.75, 78.7559) (-25.4982, 0.75, 97.1568) (-43.8991, 0.75, 102.0873) (-48.8296, 0.75, 83.6864) (-67.2305, 0.75, 88.6169) (-62.3, 0.75, 107.0178) (-68.625, 0.75, 41.975) (-62.625, 0.75, 41.975) (-62.625, 0.75, 54.475) (-64.775, 0.75, 54.475) (-64.775, 0.75, 55.475) (-66.475, 0.75, 55.475) (-66.475, 0.75, 54.475) (-68.625, 0.75, 54.475) (-54.625, 0.75, 54.625) (-40.625, 0.75, 54.625) (-40.625, 0.75, 40.625) (-54.625, 0.75, 40.625) (-32.625, 0.75, 41.975) (-26.625, 0.75, 41.975) (-26.625, 0.75, 54.475) (-28.775, 0.75, 54.475) (-28.775, 0.75, 55.475) (-30.475, 0.75, 54.475) (-32.625, 0.75, 54.475) (-30.475, 0.75, 55.475) (59.675, 0.75, 4.43) (61.025, 0.75, 20.43) (61.025, 0.75, -3.57) (73.525, 0.75, -3.57) (74.525, 0.75, -1.42) (73.525, 0.75, -1.42) (73.525, 0.75, 0.28) (74.525, 0.75, 0.28) (73.525, 0.75, 2.43) (61.025, 0.75, 2.43) (59.675, 0.75, 18.43) (61.025, 0.75, 26.43) (73.675, 0.75, 18.43) (74.525, 0.75, 24.28) (73.525, 0.75, 24.28) (73.525, 0.75, 26.43) (73.675, 0.75, 4.43) (73.525, 0.75, 20.43) (73.525, 0.75, 22.58) (74.525, 0.75, 22.58) (48.15, 0.75, 34.355) (64.15, 0.75, 33.005) (72.15, 0.75, 34.355) (50.15, 0.75, 33.005) (66.15, 0.75, 34.355) (42.15, 0.75, 34.355) (50.15, 0.75, 47.005) (46, 0.75, 46.855) (44.3, 0.75, 47.855) (44.3, 0.75, 46.855) (42.15, 0.75, 46.855) (70, 0.75, 46.855) (68.3, 0.75, 47.855) (68.3, 0.75, 46.855) (66.15, 0.75, 46.855) (48.15, 0.75, 46.855) (72.15, 0.75, 46.855) (70, 0.75, 47.855) (46, 0.75, 47.855) (-73.675, 0.75, 21.575) (-73.675, 0.75, 2.525) (-73.675, 0.75, -16.525) (-73.675, 0.75, -35.575) (-73.675, 0.75, -54.625) (-54.625, 0.75, -54.625) (-54.625, 0.75, -35.575) (-54.625, 0.75, -16.525) (-54.625, 0.75, 2.525) (-54.625, 0.75, 21.575) (-35.575, 0.75, 15.86) (-35.575, 0.75, -3.19) (-35.575, 0.75, -22.24) (-35.575, 0.75, -41.29) (-35.575, 0.75, -60.34) (-16.525, 0.75, -52.72) (-16.525, 0.75, -33.67) (-16.525, 0.75, -14.62) (-16.525, 0.75, 4.43) (-16.525, 0.75, 23.48) (-16.525, 0.75, 42.53) (2.525, 0.75, 52.055) (2.525, 0.75, 33.005) (2.525, 0.75, 13.955) (2.525, 0.75, -5.095) (2.525, 0.75, -24.145) (2.525, 0.75, -43.195) (21.575, 0.75, -43.195) (40.625, 0.75, -43.195) (59.675, 0.75, -43.195) (59.675, 0.75, -24.145) (40.625, 0.75, -24.145) (21.575, 0.75, -24.145) (21.575, 0.75, -5.095) (40.625, 0.75, -5.095) (40.625, 0.75, 13.955) (21.575, 0.75, 13.955) (21.575, 0.75, 33.005) (21.575, 0.75, 52.055) (40.625, 0.75, 52.055) (-59.675, 0.75, 21.575) (-40.625, 0.75, 21.575) (-21.575, 0.75, 15.86) (-21.575, 0.75, -3.19) (-40.625, 0.75, 2.525) (-59.675, 0.75, 2.525) (-59.675, 0.75, -16.525) (-40.625, 0.75, -16.525) (-21.575, 0.75, -22.24) (-21.575, 0.75, -41.29) (-40.625, 0.75, -35.575) (-59.675, 0.75, -35.575) (-59.675, 0.75, -54.625) (-40.625, 0.75, -54.625) (-21.575, 0.75, -60.34) (-2.525, 0.75, -52.72) (-2.525, 0.75, -33.67) (-2.525, 0.75, -14.62) (-2.525, 0.75, 4.43) (-2.525, 0.75, 23.48) (-2.525, 0.75, 42.53) (16.525, 0.75, 52.055) (35.575, 0.75, 52.055) (35.575, 0.75, 33.005) (16.525, 0.75, 33.005) (16.525, 0.75, 13.955) (35.575, 0.75, 13.955) (54.625, 0.75, 13.955) (54.625, 0.75, -5.095) (35.575, 0.75, -5.095) (16.525, 0.75, -5.095) (16.525, 0.75, -24.145) (16.525, 0.75, -43.195) (35.575, 0.75, -43.195) (35.575, 0.75, -24.145) (54.625, 0.75, -24.145) (54.625, 0.75, -43.195) (73.675, 0.75, -43.195) (73.675, 0.75, -24.145) (64.15, 0.75, 47.005) (54.625, 0.75, 66.055) (35.575, 0.75, 47.005) (16.525, 0.75, 47.005) (16.525, 0.75, 66.055) (35.575, 0.75, 66.055) (54.625, 0.75, 52.055) (54.625, 0.75, 27.955) (35.575, 0.75, 27.955) (16.525, 0.75, 27.955) (16.525, 0.75, 8.905) (35.575, 0.75, 8.905) (54.625, 0.75, 8.905) (73.675, 0.75, -10.145) (73.675, 0.75, -29.195) (54.625, 0.75, -29.195) (54.625, 0.75, -10.145) (35.575, 0.75, -10.145) (35.575, 0.75, -29.195) (16.525, 0.75, -29.195) (16.525, 0.75, -10.145) (-2.525, 0.75, -19.67) (-2.525, 0.75, -0.62) (-2.525, 0.75, 18.43) (-2.525, 0.75, 37.48) (-2.525, 0.75, 56.53) (-21.575, 0.75, 29.86) (-21.575, 0.75, 10.81) (-21.575, 0.75, -8.24) (-21.575, 0.75, -27.29) (-21.575, 0.75, -46.34) (-40.625, 0.75, -40.625) (-40.625, 0.75, -21.575) (-40.625, 0.75, -2.525) (-40.625, 0.75, 16.525) (-40.625, 0.75, 35.575) (-59.675, 0.75, 35.575) (-59.675, 0.75, 16.525) (-59.675, 0.75, -2.525) (-59.675, 0.75, -21.575) (-59.675, 0.75, -40.625) (-73.675, 0.75, -40.625) (-54.625, 0.75, -40.625) (-54.625, 0.75, -21.575) (-73.675, 0.75, -21.575) (-54.625, 0.75, -2.525) (-73.675, 0.75, -2.525) (-54.625, 0.75, 16.525) (-54.625, 0.75, 35.575) (-73.675, 0.75, 35.575) (-73.675, 0.75, 16.525) (-35.575, 0.75, 29.86) (-35.575, 0.75, 10.81) (-35.575, 0.75, -8.24) (-35.575, 0.75, -27.29) (-35.575, 0.75, -46.34) (-16.525, 0.75, -38.72) (-16.525, 0.75, -19.67) (-16.525, 0.75, -0.62) (-16.525, 0.75, 18.43) (-16.525, 0.75, 37.48) (-16.525, 0.75, 56.53) (2.525, 0.75, 66.055) (21.575, 0.75, 66.055) (21.575, 0.75, 47.005) (2.525, 0.75, 47.005) (40.625, 0.75, 66.055) (21.575, 0.75, 27.955) (2.525, 0.75, 27.955) (40.625, 0.75, 27.955) (40.625, 0.75, 8.905) (21.575, 0.75, 8.905) (2.525, 0.75, 8.905) (21.575, 0.75, -10.145) (2.525, 0.75, -10.145) (2.525, 0.75, -29.195) (21.575, 0.75, -29.195) (40.625, 0.75, -10.145) (40.625, 0.75, -29.195) (59.675, 0.75, -10.145) (59.675, 0.75, -29.195)